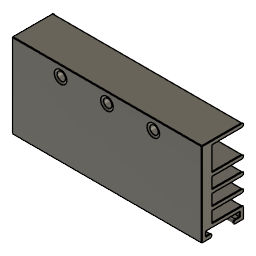
R-2010-45 (Autodesk Fusion 360 design; units mm, degrees)
part number: 2026-02-22-20-32-33-632
Autodesk Fusion 360 part; units mm, degrees
sketch "Sketch1" plane through (0, 0, 0) normal (0, 0, 1) x (1, 0, 0)
  line L0 (22.5, -5) -> (-22.5, -5)
  line L1 (-22.5, -5) -> (-22.5, 5)
  line L2 (-22.5, 5) -> (22.5, 5)
  line L3 (22.5, 5) -> (22.5, -5)
  line L4 (22.5, -5) -> (-22.5, 5) construction
  line L5 (-22.5, -5) -> (22.5, 5) construction
  dimension "d1" = 45
  dimension "d2" = 10
  constraint horizontal L0
  constraint perpendicular L0 L1
  constraint parallel L0 L2
  constraint parallel L1 L3
  constraint coincident L4 origin
  constraint coincident L5 origin
  measures "d1" distance of L1.end L2.end
  measures "d2" distance of L0.end L1.end
extrude "Extrude1" add sketch "Sketch1" along normal blind 20
sketch "Sketch2" plane through (22.5, 0, 0) normal (1, 0, 0) x (0, 1, 0)
  line L0 (-5, 0) -> (5, 0)
  line L1 (5, 0) -> (5, 20)
  line L2 (5, 20) -> (-5, 20)
  line L3 (-5, 20) -> (-5, 0)
  line L4 (-5, 3) -> (5, 3) construction
  line L5 (-5, 2) -> (5, 2) construction
  line L6 (-5, 1) -> (5, 1) construction
  line L7 (-2.5, 0) -> (-2.5, 20) construction
  line L8 (2.5, 0) -> (2.5, 20) construction
  line L9 (-5, 19) -> (5, 19) construction
  line L10 (-5, 5.5) -> (5, 5.5) construction
  line L11 (-5, 6.5) -> (5, 6.5) construction
  line L12 (-5, 9) -> (5, 9) construction
  line L13 (-5, 10) -> (5, 10) construction
  line L14 (-5, 12.5) -> (5, 12.5) construction
  line L15 (-5, 13.5) -> (5, 13.5) construction
  line L16 (-5, 0) -> (-5, 20)
  arc A0 (4.4992, 19) -> (4.5, 20) centre (4.5, 19.5) ccw
  line L17 (-5, 20) -> (4.5, 20)
  line L18 (4.4992, 19) -> (-2.5, 19)
  line L19 (-2.5, 19) -> (-2.5, 13.5)
  arc A1 (4.5, 12.5) -> (4.5, 13.5) centre (4.5, 13) ccw
  arc A2 (4.5, 9) -> (4.5, 10) centre (4.5, 9.5) ccw
  arc A3 (4.5, 5.5) -> (4.5, 6.5) centre (4.5, 6) ccw
  arc A4 (5, 2.5) -> (4.5, 3) centre (4.5, 2.5) ccw
  arc A5 (4.5, 0) -> (5, 0.5) centre (4.5, 0.5) ccw
  line L20 (-2.5, 13.5) -> (4.5, 13.5)
  line L21 (4.5, 12.5) -> (-2.5, 12.5)
  line L22 (-2.5, 12.5) -> (-2.5, 10)
  line L23 (-2.5, 10) -> (4.5, 10)
  line L24 (4.5, 9) -> (-2.5, 9)
  line L25 (-2.5, 9) -> (-2.5, 6.5)
  line L26 (-2.5, 6.5) -> (4.5, 6.5)
  line L27 (4.5, 5.5) -> (-2.5, 5.5)
  line L28 (-2.5, 5.5) -> (-2.5, 3)
  line L29 (-2.5, 3) -> (4.5, 3)
  line L30 (5, 2) -> (5, 0.5)
  line L31 (5, 2) -> (5, 2.5)
  arc A6 (3, 1) -> (3, 0) centre (3, 0.5) ccw
  arc A7 (-3, 0) -> (-3, 1) centre (-3, 0.5) ccw
  line L32 (-4, 0) -> (-4, 20) construction
  line L33 (4, 0) -> (4, 20) construction
  line L34 (4.5, 0) -> (3, 0)
  line L35 (3, 1) -> (4, 1)
  line L36 (4, 1) -> (4, 2)
  line L37 (4, 2) -> (-4, 2)
  line L38 (-4, 2) -> (-4, 1)
  line L39 (-3, 1) -> (-4, 1)
  line L40 (-3, 0) -> (-5, 0)
  dimension "d5" = 10
  dimension "d6" = 3
  dimension "d7" = 1
  dimension "d8" = 2
  dimension "d9" = 20
  dimension "d10" = 2.5
  dimension "d11" = 20
  dimension "d12" = 2.5
  dimension "d13" = 10
  dimension "d14" = 1
  dimension "d15" = 10
  dimension "d16" = 2.5
  dimension "d17" = 10
  dimension "d18" = 1
  dimension "d19" = 10
  dimension "d20" = 2.5
  dimension "d21" = 10
  dimension "d22" = 1
  dimension "d23" = 10
  dimension "d24" = 2.5
  dimension "d25" = 10
  dimension "d26" = 1
  dimension "d27" = 0.5
  dimension "d28" = 0.5
  dimension "d29" = 20
  dimension "d30" = 1
  dimension "d31" = 20
  dimension "d32" = 1
  constraint coincident L3 L4.start
  constraint perpendicular L1 L4
  constraint coincident L3 L5.start
  constraint coincident L1 L5.end
  constraint perpendicular L1 L5
  constraint coincident L3 L6.start
  constraint coincident L1 L6.end
  constraint perpendicular L1 L6
  constraint coincident L0 L7.start
  constraint perpendicular L2 L7
  constraint coincident L0 L8.start
  constraint perpendicular L2 L8
  constraint coincident L3 L9.start
  constraint perpendicular L8 L9
  constraint coincident L3 L10.start
  constraint perpendicular L1 L10
  constraint coincident L3 L11.start
  constraint perpendicular L1 L11
  constraint coincident L3 L12.start
  constraint perpendicular L1 L12
  constraint coincident L3 L13.start
  constraint perpendicular L1 L13
  constraint coincident L3 L14.start
  constraint perpendicular L1 L14
  constraint horizontal L15
  constraint coincident L3 L15.start
  constraint coincident L0.start L3.end
  constraint coincident L2.end L3.start
  constraint coincident L9 A0.start
  constraint tangent A0 L17
  constraint coincident L9 L18.end
  constraint coincident L7 L18.end
  constraint coincident L15 L19.end
  constraint coincident L7 L19.end
  constraint coincident L14 A1.start
  constraint coincident L13 A2.end
  constraint coincident L10 A3.start
  constraint coincident L11 A3.end
  constraint coincident L1 A4.start
  constraint coincident L4 A4.end
  constraint coincident L0 A5.start
  constraint coincident L1 A5.end
  constraint tangent A1 L20
  constraint coincident L14 L21.end
  constraint coincident L7 L21.end
  constraint midpoint L7 L22.end
  constraint tangent A2 L23
  constraint coincident L7 L24.end
  constraint coincident L12 L24.end
  constraint coincident L7 L25.end
  constraint coincident L11 L25.end
  constraint tangent A3 L26
  constraint coincident L10 L27.end
  constraint coincident L7 L27.end
  constraint coincident L4 L28.end
  constraint coincident L7 L28.end
  constraint tangent A4 L29
  constraint tangent A5 L30
  constraint tangent A4 L31
  constraint tangent A2 L24
  constraint coincident L6 A6.start
  constraint coincident L0 A7.start
  constraint coincident L6 A7.end
  constraint vertical L32
  constraint coincident L0 L32.start
  constraint vertical L33
  constraint coincident L0 L33.start
  constraint tangent A6 L34
  constraint coincident L33 L35.end
  constraint coincident L6 L35.end
  constraint coincident L33 L36.end
  constraint coincident L5 L36.end
  constraint coincident L32 L37.end
  constraint coincident L5 L37.end
  constraint coincident L32 L38.end
  constraint coincident L6 L38.end
  constraint tangent A7 L40
  measures "d5" distance of L4.start L4.end
  measures "d6" distance of L0 L4
  measures "d7" distance of L0 L6
  measures "d8" distance of L0 L5
  measures "d9" distance of L7.start L7.end
  measures "d10" distance of L3 L7
  measures "d11" distance of L8.start L8.end
  measures "d12" distance of L1 L8
  measures "d13" distance of L9.start L9.end
  measures "d14" distance of L2 L9
  measures "d15" distance of L10.start L10.end
  measures "d16" distance of L4 L10
  measures "d17" distance of L11.start L11.end
  measures "d18" distance of L10 L11
  measures "d19" distance of L12.start L12.end
  measures "d20" distance of L11 L12
  measures "d21" distance of L13.start L13.end
  measures "d22" distance of L12 L13
  measures "d23" distance of L14.start L14.end
  measures "d24" distance of L13 L14
  measures "d25" distance of L15.start L15.end
  measures "d26" distance of L14 L15
  measures "d27" radius of A0
  measures "d28" radius of A1
  measures "d29" distance of L32.start L32.end
  measures "d30" distance of L16 L32
  measures "d31" distance of L33.start L33.end
  measures "d32" distance of L1 L33
extrude "Extrude2" cut sketch "Sketch2" against normal blind 45 contours L0 A6 A7 L35 L36 L37 L38 L39 | L1 L2 A0 | L1 A0 L18 L19 A1 L20 | L1 A1 A2 L21 L22 L23 | L1 A2 A3 L24 L25 L26 | L1 A3 A4 L27 L28 L29
sketch "Sketch3" plane through (0, -5, 0) normal (0, -1, 0) x (1, 0, 0)
  line L0 (-22.5, 0) -> (22.5, 0)
  line L1 (22.5, 0) -> (22.5, 20)
  line L2 (22.5, 20) -> (-22.5, 20)
  line L3 (-22.5, 20) -> (-22.5, 0)
  line L4 (0, 0) -> (0, 20) construction
  line L5 (-11, 0) -> (-11, 20) construction
  line L6 (11, 0) -> (11, 20) construction
  line L7 (25, 17.5) -> (-25, 17.5) construction
  circle A0 centre (-11, 17.5) radius 1
  circle A1 centre (0, 17.5) radius 1
  circle A2 centre (11, 17.5) radius 1
  point P0 (-11, 17.5)
  point P1 (0, 17.5)
  point P2 (11, 17.5)
  dimension "d35" = 20
  dimension "d36" = 20
  dimension "d37" = 20
  dimension "d38" = 11
  dimension "d39" = 11
  dimension "d40" = 50
  dimension "d41" = 2.5
  dimension "d42" = 2
  dimension "d43" = 2
  dimension "d44" = 2
  constraint vertical L4
  constraint coincident L4.start origin
  constraint vertical L5
  constraint coincident L0 L5.start
  constraint vertical L6
  constraint coincident L0 L6.start
  constraint horizontal L7
  constraint coincident L5 P0
  constraint coincident L7 P0
  constraint midpoint L7 P1
  constraint coincident L6 P2
  constraint coincident L7 P2
  constraint coincident P0 A0.centre
  constraint coincident P1 A1.centre
  constraint coincident P2 A2.centre
  measures "d35" distance of L4.start L4.end
  measures "d36" distance of L5.start L5.end
  measures "d37" distance of L6.start L6.end
  measures "d38" distance of L4 L5
  measures "d39" distance of L4 L6
  measures "d40" distance of L7.start L7.end
  measures "d41" distance of L2 L7
  measures "d42" diameter of A0
  measures "d43" diameter of A1
  measures "d44" diameter of A2
extrude "Extrude3" cut sketch "Sketch3" against normal blind 2.5 contours A0 | A1 | A2
chamfer "Chamfer1" distance 0.5 distance2 0.2 3 edges at (-11.9323, -5, 17.8616) (-0.9323, -5, 17.8616) (10.0677, -5, 17.8616) measured on face at (-0.0249, -5, 5.5009) measured on face at (-0.0249, -5, 5.5009) measured on face at (-0.0249, -5, 5.5009)
fillet "Fillet1" radius 0.1 60 edges at (-22.5, -5, 10) (-22.5, -3.5, 1) (-22.5, -2.5, 0.5) (-22.5, -4, 0) (-22.5, -4, 1.5) (-22.5, 0, 2) (-22.5, 4, 1.5) (-22.5, 4, 0) (-22.5, 2.5, 0.5) (-22.5, 3.5, 1) (-22.5, 5, 1.25) (-22.5, 4.8536, 2.8536) (-22.5, 1, 3) (-22.5, -2.5, 4.25) (-22.5, 1, 6.5) (-22.5, 5, 6) (-22.5, 1, 5.5) (-22.5, -2.5, 7.75) (-22.5, 1, 10) (-22.5, 5, 9.5) (-22.5, 1, 9) (-22.5, -2.5, 11.25) (-22.5, 1, 13.5) (-22.5, 5, 13) (-22.5, 1, 12.5) (-22.5, -2.5, 16.25) (-22.5, -0.25, 20) (-22.5, 5, 19.4996) (-22.5, 0.9996, 19) (0, -5, 20) (22.5, -5, 10) (22.5, -0.25, 20) (22.5, 5, 19.4996) (22.5, 0.9996, 19) (22.5, -2.5, 16.25) (22.5, 1, 12.5) (22.5, 5, 13) (22.5, 1, 13.5) (22.5, 1, 9) (22.5, 5, 9.5) (22.5, 1, 10) (22.5, -2.5, 11.25) (22.5, -2.5, 7.75) (22.5, 1, 5.5) (22.5, 5, 6) (22.5, 1, 6.5) (22.5, -2.5, 4.25) (22.5, 5, 1.25) (22.5, 4.8536, 2.8536) (22.5, 1, 3) (22.5, 4, 1.5) (22.5, 0, 2) (22.5, -4, 1.5) (22.5, -4, 0) (22.5, -2.5, 0.5) (22.5, -3.5, 1) (22.5, 3.5, 1) (22.5, 2.5, 0.5) (22.5, 4, 0) (0, -5, 0)
